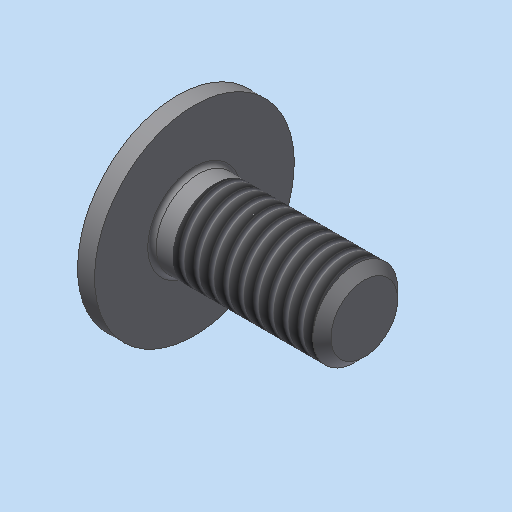
# Autodesk Inventor part: Flk_Schr_m_Fl_DIN7380-2_M4x8_10-9_VZ
Saved by Autodesk Inventor 2023.3 (Build 273359000, 359)
## iProperties
Shininess: 64.0
Length Units: 11269
Angle Units: 11279
Time Units: 11290
Mass Units: 11283
Length Display Precision: 3
Angle Display Precision: 2
Compacted: True
Part Number: Flk_Schr_m_Fl_DIN7380-2_M4x8_10-9_VZ
Document SubType Name: Modeling
Created: 2004-04-02
Material: xStahl_AnP_Dummymaterial
Description: =<RBPARTNOTITLE2>
Vendor: NORM8
Designer: S.Riedelsheimer
Manufacturer: Standard
Standards Organization: Custom
Mass: 1.43768 g
Surface Area: 2.8062 cm^2
Volume: 0.183144 cm^3
Density: 7.85 g/cm^3
Appearance: RGB(178,178,178)
Density: 0.0
Volumn: 0.0
Area: 0.0
PropertySet Name: Model Information
Control State: 0
Master: False
Checked Out: False
CNS_NB: Hexagon socket button head screw ISO7380-M4x8
CNS_NN: ISO 7380
CNS_NT: Hexagon socket button head screw
CNS_NBSYN: Hexagon socket button head screw ISO7380-M$D.x$L.
CNS_LINA: Hexagon socket button head screw ISO7380-M4x8
CNS_D: 4.000
CNS_D3: 3.141
CNS_P: 0.700
CNS_L: 8.000
CNS_S: 2.500
CNS_A: 1.400
CNS_DA: 4.700
CNS_DK: 7.600
CNS_K: 2.200
CNS_R: 0.200
CNS_T: 1.300
CNS_KT: DUMMY
PSOL_IDENT_0: {C:\partsolutions8\data\23d-libs\bosch_bamberg\schrauben\spezialschrauben\iso_7380.prj},181 {M=Nenng
PSOL_IDENT_1: ewinde},{VTYP=3D},{NB=Hexagon socket button head screw ISO7380-M4x8},{NN=ISO 7380},{DATE=26.11.2003}
PSOL_IDENT_2: ,{GEOMDATE=26.11.2003},{VERSION=v1},{LINEID=50},{LINESUBID=-1},{WBVAR=}  {NB=Hexagon socket button h
PSOL_IDENT_3: ead screw ISO7380-M4x8},{LINA=Hexagon socket button head screw ISO7380-M4x8},{KT=DUMMY},{IDNR=},{D=4
PSOL_IDENT_4: .000},{D3=3.141},{P=0.700},{L=8.000},{S=2.500},{A=1.400},{DA=4.700},{DK=7.600},{K=2.200},{R=0.200},{
PSOL_IDENT_5: T=1.300}
RBPARTNOTITLE2: Schraube mit abgeflachtem halbrundkopf und Innensechskant
RBPARTNOTITLE1: Hexagon socket button head screw
RBPARTMADEOF: ISO 7380-2 - M4x8 - St
RBDRAWINGMISSINGSPEC: --
AnP_Kategorie: 2
Title: Hexagon socket button head screw ISO7380-M4x8
Author: S.Riedelsheimer
Keywords: =<RBPARTMADEOF>
Comments: =<RBSURFACE2>
Revision Number: 01
Autodesk Inventor part; units mm, degrees
sketch "Sketch_1" plane through (0, 0, 0) normal (0, 1, 0) x (-1, 0, 0)
  line L0 (0.236, 0) -> (-8, 0)
  line L1 (-8, 0) -> (-8, 1.5705)
  line L2 (-8, 1.5705) -> (-7.5705, 2)
  line L3 (-7.5705, 2) -> (-0.2, 2)
  arc A0 (-0.2, 2) -> (0, 2.2) centre (-0.2, 2.2) ccw
  line L4 (0, 2.2) -> (0, 3.8)
  arc A1 (2.2, 2) -> (0, 3.8) centre (-1.2727, 0) ccw
  line L5 (2.2, 2) -> (2.2, 1.4434)
  line L6 (2.2, 1.4434) -> (1.9066, 1.15)
  line L7 (1.9066, 1.15) -> (0.9, 1.15)
  line L8 (0.9, 1.15) -> (0.236, 0)
  line L9 (0.236, 0) -> (-8, 0)
  constraints: 20 end point, 4 point on circle, 2 centre point
revolve "Drehung1" add sketch "Sketch_1" angle 360 about axis through (-0.236, 0, 0) along (1, 0, 0)
thread "Gewinde1" size "M4x0.7" class "6g" standard "ANSI Metric M Profile" length 6.6
sketch "Sketch_2" plane through (-2.2, 0, 0) normal (1, 0, 0) x (0, 0, -1)
  line L0 (-1.25, 0.7217) -> (-1.25, -0.7217)
  line L1 (-1.25, -0.7217) -> (0, -1.4434)
  line L2 (0, -1.4434) -> (1.25, -0.7217)
  line L3 (1.25, -0.7217) -> (1.25, 0.7217)
  line L4 (1.25, 0.7217) -> (0, 1.4434)
  line L5 (0, 1.4434) -> (-1.25, 0.7217)
  constraints: 12 end point
extrude "Extrusion1" cut sketch "Sketch_2" along normal blind 1.3
ref_plane "IP1_XY" through (0, 0, 0) normal (1, 0, 0) x (0, 0, -1)
ref_plane "IP1_YZ" through (0, 0, 0) normal (0, 0, -1) x (0, 1, 0)
ref_plane "IP2_XY" through (8, 0, 0) normal (1, 0, 0) x (0, 0, -1)
ref_plane "IP2_YZ" through (8, 0, 0) normal (0, 0, -1) x (0, 1, 0)
sketch "Skizze3" plane through (0, 0, 0) normal (0, 1, 0) x (-1, 0, 0)
  line L0 (0, -5.32) -> (0, 5.32) projected
  line L1 (-10.04, 0) -> (4.24, 0) projected
  line L2 (0, 0) -> (0.8, 0)
  line L3 (0.8, 0) -> (0.8, 4.7)
  line L4 (0.8, 4.7) -> (0, 4.7)
  line L5 (0, 4.7) -> (0, 0)
  arc A0 (0, -3.8) -> (0, 3.8) centre (-1.2727, 0) ccw projected
  point P0 (0.8, 3.4298)
  dimension "d5" = 4.7
  dimension "d6" = 0.8
  constraints: 8 end point, 2 parallel, 1 horizontal, 1 perpendicular
  measures "d5" distance of L2.end L3.end
  measures "d6" distance of L3.end L4.end
revolve "Umdrehung2" add sketch "Skizze3" angle 360 about axis through (0, 0, 0) along (-1, 0, 0) contours L0 L4 L3 A0
